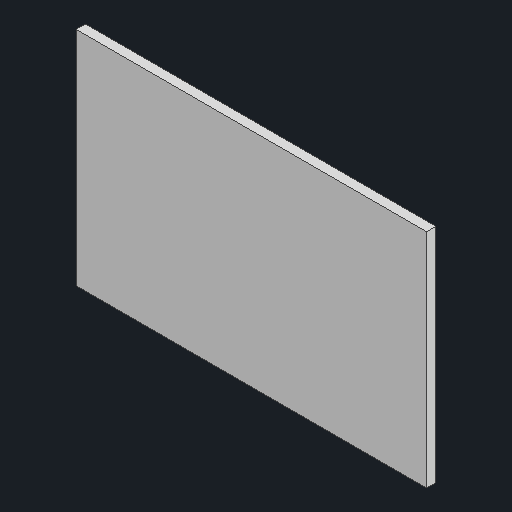
# Autodesk Inventor part: DUMMY-PROTO
Saved by Autodesk Inventor 2027.1 (Build 311270010, 270A)
## iProperties
Created: 2026-10-28
Part Number: DUMMY-PROTO
Material: Generic
Description: Protoboard + wiring
Document SubType Name: Modeling
Designer: shyan
Density: 1 g/cm^3
Appearance: Default
Mass: 20 g
Author: shyan
Autodesk Inventor part; units mm, degrees
ref_plane "YZ Plane" through (0, 0, 0) normal (1, 0, 0) x (0, 1, 0)
ref_plane "XZ Plane" through (0, 0, 0) normal (0, 1, 0) x (-1, 0, 0)
ref_plane "XY Plane" through (0, 0, 0) normal (0, 0, 1) x (1, 0, 0)
sketch "sk_body" plane through (0, 0, 0) normal (0, 0, 1) x (1, 0, 0)
  line L0 (-30, -19) -> (30, -19)
  line L1 (30, -19) -> (30, 19)
  line L2 (30, 19) -> (-30, 19)
  line L3 (-30, 19) -> (-30, -19)
  line L4 (-42, 0) -> (42, 0) construction
  line L5 (0, -28) -> (0, 28) construction
  point P0 (0, 0)
  dimension "d0" = 60
  dimension "d1" = 38
  constraints: 8 end point, 2 parallel, 1 horizontal, 1 perpendicular, 2 other
  measures "d0" distance of L0.start L0.end
  measures "d1" distance of L0.end L1.end
extrude "Body" add sketch "sk_body" along normal blind 1.6
equation "\"d0\" = pcb_W"
equation "\"d1\" = pcb_D"
equation "\"d2\" = pcb_T"
equation "\"pcb_W\" = 60"
equation "\"pcb_D\" = 38"
equation "\"pcb_T\" = 1.6"
body "Solid1"
